Autodesk Fusion 360 part; units mm, degrees
(part 4 of 4)
equation "d8976 = ( fb_y0 + fb_d - 2 * fb_t ) + sk_ref"
equation "d8977 = ( -pod_d / 2 + decor_d - dr_back_t ) + sk_ref"
equation "d8978 = ( op_z0 ) * ( 1 )"
equation "d8979 = ( fb_z0 + fb_h ) - ( op_z0 )"
equation "d8981 = sk_ref"
equation "d8982 = sk_ref"
equation "d8983 = ( ( ( ( fg_rc + dr_fo ) - ( fg_vis_zb * fg_rnz ) ) / fg_rnx ) ) + sk_ref"
equation "d8984 = ( ( -( -( ( dr_fc - dr_fo - dr_fny * ( -pod_d / 2 + dr_fo ) ) / dr_fnx ) ) ) ) + sk_ref"
equation "d8985 = ( ( -( ( -( ( dr_fc - dr_fo - dr_fny * ( -pod_d / 2 + dr_fo ) ) / dr_fnx ) + 0 mm + fr_w ) ) ) ) + sk_ref"
equation "d8986 = ( ( ( ( fg_rc + dr_fo + fr_w ) - ( ( ( fg_vis_zb + 0 mm + fr_w ) ) * fg_rnz ) ) / fg_rnx ) ) + sk_ref"
equation "d8987 = ( ( ( fg_rnx * fg_vis_zb ) / fg_rnx ) ) + sk_ref"
equation "d8988 = ( ( -( -( ( fg_vis_zb + 0 mm + fr_w ) ) ) ) ) + sk_ref"
equation "d8989 = ( ( -pod_d / 2 + dr_fo ) ) * ( 1 )"
equation "d8990 = ( ( -pod_d / 2 + dr_fo + fr_w ) ) - ( ( -pod_d / 2 + dr_fo ) )"
equation "d8992 = fr_t_sk"
equation "d8993 = sk_ref"
equation "d8994 = sk_ref"
equation "d8995 = ( ( -( -( ( dr_fc - dr_fo - dr_fny * ( -pod_d / 2 + dr_fo ) ) / dr_fnx ) ) ) ) + sk_ref"
equation "d8996 = ( ( -( ( -( ( dr_fc - dr_fo - dr_fny * ( -pod_d / 2 + dr_fo ) ) / dr_fnx ) + 0 mm + fr_w ) ) ) ) + sk_ref"
equation "d8997 = ( ( -( -fg_vis_zb ) ) ) + sk_ref"
equation "d8998 = ( ( -( -( ( dr_cc - dr_fo - dr_cny * ( -pod_d / 2 + dr_fo ) ) / dr_cnz ) ) ) ) + sk_ref"
equation "d8999 = ( ( -( ( -( ( dr_cc - dr_fo - dr_cny * ( -pod_d / 2 + dr_fo ) ) / dr_cnz ) + 0 mm + fr_w ) ) ) ) + sk_ref"
equation "d9000 = ( ( -( -( ( fg_vis_zb + 0 mm + fr_w ) ) ) ) ) + sk_ref"
equation "d9001 = ( ( -pod_d / 2 + dr_fo ) ) * ( 1 )"
equation "d9002 = ( ( -pod_d / 2 + dr_fo + fr_w ) ) - ( ( -pod_d / 2 + dr_fo ) )"
equation "d9004 = fr_t_sk"
equation "d9005 = sk_ref"
equation "d9006 = sk_ref"
equation "d9007 = ( ( -( -( ( dr_fc - dr_fo - dr_fny * ( -pod_d / 2 + dr_fo ) ) / dr_fnx ) ) ) ) + sk_ref"
equation "d9008 = ( ( -( -( ( -pod_w / 2 + fix_xtr + ( ( -pod_d / 2 + dr_fo + fr_w ) - -pod_d / 2 ) * ( dt_xr - fix_xtr ) / ( pod_d / 2 - ch_yb ) ) ) ) ) ) + sk_ref"
equation "d9009 = ( ( -( -( ( ( -pod_w / 2 + fix_xtr + ( ( -pod_d / 2 + dr_fo + fr_w ) - -pod_d / 2 ) * ( dt_xr - fix_xtr ) / ( pod_d / 2 - ch_yb ) ) + 0 mm + fr_w ) ) ) ) ) + sk_ref"
equation "d9010 = ( ( -( ( -( ( dr_fc - dr_fo - dr_fny * ( -pod_d / 2 + dr_fo ) ) / dr_fnx ) + 0 mm + fr_w ) ) ) ) + sk_ref"
equation "d9011 = ( ( -( -( ( dr_cc - dr_fo - dr_cny * ( -pod_d / 2 + dr_fo ) ) / dr_cnz ) ) ) ) + sk_ref"
equation "d9012 = ( ( -( ( -( ( dr_cc - dr_fo - dr_cny * ( -pod_d / 2 + dr_fo ) ) / dr_cnz ) + 0 mm + fr_w ) ) ) ) + sk_ref"
equation "d9013 = ( ( -pod_d / 2 + dr_fo ) ) * ( 1 )"
equation "d9014 = ( ( -pod_d / 2 + dr_fo + fr_w ) ) - ( ( -pod_d / 2 + dr_fo ) )"
equation "d9016 = fr_t_sk"
equation "d9017 = sk_ref"
equation "d9018 = sk_ref"
equation "d9019 = ( ( -( -( ( -pod_w / 2 + fix_xtr + ( ( -pod_d / 2 + dr_fo + fr_w ) - -pod_d / 2 ) * ( dt_xr - fix_xtr ) / ( pod_d / 2 - ch_yb ) ) ) ) ) ) + sk_ref"
equation "d9020 = ( ( ( ( ( ( -pod_w / 2 + fix_xtr + ( ( -pod_d / 2 + dr_fo + fr_w ) - -pod_d / 2 ) * ( dt_xr - fix_xtr ) / ( pod_d / 2 - ch_yb ) ) + 0 mm + fr_w ) ) * fg_dnz ) / fg_dnz ) ) + sk_ref"
equation "d9021 = ( ( -( -( ( dr_cc - dr_fo - dr_cny * ( -pod_d / 2 + dr_fo ) ) / dr_cnz ) ) ) ) + sk_ref"
equation "d9022 = ( ( ( ( fg_dc + dr_fo ) - ( fg_dnx * ( ( -pod_w / 2 + fix_xtr + ( ( -pod_d / 2 + dr_fo + fr_w ) - -pod_d / 2 ) * ( dt_xr - fix_xtr ) / ( pod_d / 2 - ch_yb ) ) ) ) ) / fg_dnz ) ) + sk_ref"
equation "d9023 = ( ( ( ( fg_dc + dr_fo + fr_w ) - ( fg_dnx * ( ( ( -pod_w / 2 + fix_xtr + ( ( -pod_d / 2 + dr_fo + fr_w ) - -pod_d / 2 ) * ( dt_xr - fix_xtr ) / ( pod_d / 2 - ch_yb ) ) + 0 mm + fr_w ) ) ) ) / fg_dnz ) ) + sk_ref"
equation "d9024 = ( ( -( ( -( ( dr_cc - dr_fo - dr_cny * ( -pod_d / 2 + dr_fo ) ) / dr_cnz ) + 0 mm + fr_w ) ) ) ) + sk_ref"
equation "d9025 = ( ( -pod_d / 2 + dr_fo ) ) * ( 1 )"
equation "d9026 = ( ( -pod_d / 2 + dr_fo + fr_w ) ) - ( ( -pod_d / 2 + dr_fo ) )"
equation "d9028 = fr_t_sk"
equation "d9029 = sk_ref"
equation "d9030 = sk_ref"
equation "d9031 = ( ( ( ( ( -pod_w / 2 + fix_xtr + ( ( -pod_d / 2 + dr_fo + fr_w ) - -pod_d / 2 ) * ( dt_xr - fix_xtr ) / ( pod_d / 2 - ch_yb ) ) ) * fg_dnz ) / fg_dnz ) ) + sk_ref"
equation "d9032 = ( ( ( ( ( fg_dc + dr_fo ) ) * fg_rnz - ( ( ( fg_rc + dr_fo ) ) * fg_dnz ) ) / ( fg_dnx * fg_rnz - ( fg_rnx * fg_dnz ) ) ) ) + sk_ref"
equation "d9033 = ( ( ( ( ( fg_dc + dr_fo + fr_w ) ) * fg_rnz - ( ( ( fg_rc + dr_fo + fr_w ) ) * fg_dnz ) ) / ( fg_dnx * fg_rnz - ( fg_rnx * fg_dnz ) ) ) ) + sk_ref"
equation "d9034 = ( ( ( ( ( ( -pod_w / 2 + fix_xtr + ( ( -pod_d / 2 + dr_fo + fr_w ) - -pod_d / 2 ) * ( dt_xr - fix_xtr ) / ( pod_d / 2 - ch_yb ) ) + 0 mm + fr_w ) ) * fg_dnz ) / fg_dnz ) ) + sk_ref"
equation "d9035 = ( ( ( ( fg_dc + dr_fo ) - ( fg_dnx * ( ( -pod_w / 2 + fix_xtr + ( ( -pod_d / 2 + dr_fo + fr_w ) - -pod_d / 2 ) * ( dt_xr - fix_xtr ) / ( pod_d / 2 - ch_yb ) ) ) ) ) / fg_dnz ) ) + sk_ref"
equation "d9036 = ( ( ( fg_dnx * ( ( fg_rc + dr_fo ) ) - ( fg_rnx * ( ( fg_dc + dr_fo ) ) ) ) / ( fg_dnx * fg_rnz - ( fg_rnx * fg_dnz ) ) ) ) + sk_ref"
equation "d9037 = ( ( ( fg_dnx * ( ( fg_rc + dr_fo + fr_w ) ) - ( fg_rnx * ( ( fg_dc + dr_fo + fr_w ) ) ) ) / ( fg_dnx * fg_rnz - ( fg_rnx * fg_dnz ) ) ) ) + sk_ref"
equation "d9038 = ( ( ( ( fg_dc + dr_fo + fr_w ) - ( fg_dnx * ( ( ( -pod_w / 2 + fix_xtr + ( ( -pod_d / 2 + dr_fo + fr_w ) - -pod_d / 2 ) * ( dt_xr - fix_xtr ) / ( pod_d / 2 - ch_yb ) ) + 0 mm + fr_w ) ) ) ) / fg_dnz ) ) + sk_ref"
equation "d9039 = ( ( -pod_d / 2 + dr_fo ) ) * ( 1 )"
equation "d9040 = ( ( -pod_d / 2 + dr_fo + fr_w ) ) - ( ( -pod_d / 2 + dr_fo ) )"
equation "d9042 = fr_t_sk"
equation "d9043 = sk_ref"
equation "d9044 = sk_ref"
equation "d9045 = ( ( ( ( ( fg_dc + dr_fo ) ) * fg_rnz - ( ( ( fg_rc + dr_fo ) ) * fg_dnz ) ) / ( fg_dnx * fg_rnz - ( fg_rnx * fg_dnz ) ) ) ) + sk_ref"
equation "d9046 = ( ( ( ( fg_rc + dr_fo ) - ( fg_vis_zb * fg_rnz ) ) / fg_rnx ) ) + sk_ref"
equation "d9047 = ( ( ( ( fg_rc + dr_fo + fr_w ) - ( ( ( fg_vis_zb + 0 mm + fr_w ) ) * fg_rnz ) ) / fg_rnx ) ) + sk_ref"
equation "d9048 = ( ( ( ( ( fg_dc + dr_fo + fr_w ) ) * fg_rnz - ( ( ( fg_rc + dr_fo + fr_w ) ) * fg_dnz ) ) / ( fg_dnx * fg_rnz - ( fg_rnx * fg_dnz ) ) ) ) + sk_ref"
equation "d9049 = ( ( ( fg_dnx * ( ( fg_rc + dr_fo ) ) - ( fg_rnx * ( ( fg_dc + dr_fo ) ) ) ) / ( fg_dnx * fg_rnz - ( fg_rnx * fg_dnz ) ) ) ) + sk_ref"
equation "d9050 = ( ( ( fg_rnx * fg_vis_zb ) / fg_rnx ) ) + sk_ref"
equation "d9051 = ( ( ( fg_rnx * ( ( fg_vis_zb + 0 mm + fr_w ) ) ) / fg_rnx ) ) + sk_ref"
equation "d9052 = ( ( ( fg_dnx * ( ( fg_rc + dr_fo + fr_w ) ) - ( fg_rnx * ( ( fg_dc + dr_fo + fr_w ) ) ) ) / ( fg_dnx * fg_rnz - ( fg_rnx * fg_dnz ) ) ) ) + sk_ref"
equation "d9053 = ( ( -pod_d / 2 + dr_fo ) ) * ( 1 )"
equation "d9054 = ( ( -pod_d / 2 + dr_fo + fr_w ) ) - ( ( -pod_d / 2 + dr_fo ) )"
equation "d9056 = fr_t_sk"
equation "d9057 = sk_ref"
equation "d9058 = sk_ref"
equation "d9059 = ( ( ( ( fg_rc + dr_fo ) - ( fg_vis_zb * fg_rnz ) ) / fg_rnx ) ) + sk_ref"
equation "d9060 = ( ( -( ( -pod_w / 2 + dr_fo ) ) ) ) + sk_ref"
equation "d9061 = ( ( -( ( -pod_w / 2 + dr_fo + fr_wb ) ) ) ) + sk_ref"
equation "d9062 = ( ( ( ( fg_rc + dr_fo + fr_w ) - ( ( ( fg_vis_zb + 0 mm + fr_wbot ) ) * fg_rnz ) ) / fg_rnx ) ) + sk_ref"
equation "d9063 = ( ( ( fg_rnx * fg_vis_zb ) / fg_rnx ) ) + sk_ref"
equation "d9064 = ( ( -( -( ( fg_vis_zb + 0 mm + fr_wbot ) ) ) ) ) + sk_ref"
equation "d9065 = ( ( -pod_d / 2 + decor_d - dr_back_t - fr_w ) ) * ( 1 )"
equation "d9066 = ( ( -pod_d / 2 + decor_d - dr_back_t ) ) - ( ( -pod_d / 2 + decor_d - dr_back_t - fr_w ) )"
equation "d9068 = fr_t_pnl"
equation "d9069 = sk_ref"
equation "d9070 = sk_ref"
equation "d9071 = ( ( -( ( -pod_w / 2 + dr_fo ) ) ) ) + sk_ref"
equation "d9072 = ( ( -( ( -pod_w / 2 + dr_fo + fr_wb ) ) ) ) + sk_ref"
equation "d9073 = ( ( -( -fg_vis_zb ) ) ) + sk_ref"
equation "d9074 = ( ( -( ( -pod_h + dr_fo ) ) ) ) + sk_ref"
equation "d9075 = ( ( -( ( -pod_h + dr_fo + fr_w ) ) ) ) + sk_ref"
equation "d9076 = ( ( -( -( ( fg_vis_zb + 0 mm + fr_wbot ) ) ) ) ) + sk_ref"
equation "d9077 = ( ( -pod_d / 2 + decor_d - dr_back_t - fr_w ) ) * ( 1 )"
equation "d9078 = ( ( -pod_d / 2 + decor_d - dr_back_t ) ) - ( ( -pod_d / 2 + decor_d - dr_back_t - fr_w ) )"
equation "d9080 = fr_t_pnl"
equation "d9081 = sk_ref"
equation "d9082 = sk_ref"
equation "d9083 = ( ( -( ( -pod_w / 2 + dr_fo ) ) ) ) + sk_ref"
equation "d9084 = ( ( -( -( ( -pod_w / 2 + dt_xr ) ) ) ) ) + sk_ref"
equation "d9085 = ( ( -( -( ( ( -pod_w / 2 + dt_xr ) + 0 mm + fr_w ) ) ) ) ) + sk_ref"
equation "d9086 = ( ( -( ( -pod_w / 2 + dr_fo + fr_wb ) ) ) ) + sk_ref"
equation "d9087 = ( ( -( ( -pod_h + dr_fo ) ) ) ) + sk_ref"
equation "d9088 = ( ( -( ( -pod_h + dr_fo + fr_w ) ) ) ) + sk_ref"
equation "d9089 = ( ( -pod_d / 2 + decor_d - dr_back_t - fr_w ) ) * ( 1 )"
equation "d9090 = ( ( -pod_d / 2 + decor_d - dr_back_t ) ) - ( ( -pod_d / 2 + decor_d - dr_back_t - fr_w ) )"
equation "d9092 = fr_t_sk"
equation "d9093 = sk_ref"
equation "d9094 = sk_ref"
equation "d9095 = ( ( -( -( ( -pod_w / 2 + dt_xr ) ) ) ) ) + sk_ref"
equation "d9096 = ( ( -( -( ( ( -pod_w / 2 + dt_xr ) + 0 mm + fr_w ) ) ) ) ) + sk_ref"
equation "d9097 = ( ( -( ( -pod_h + dr_fo ) ) ) ) + sk_ref"
equation "d9098 = ( ( -( -dt_zb ) ) ) + sk_ref"
equation "d9099 = ( ( -( ( -dt_zb + 0 mm + fr_w ) ) ) ) + sk_ref"
equation "d9100 = ( ( -( ( -pod_h + dr_fo + fr_w ) ) ) ) + sk_ref"
equation "d9101 = ( ( -pod_d / 2 + decor_d - dr_back_t - fr_w ) ) * ( 1 )"
equation "d9102 = ( ( -pod_d / 2 + decor_d - dr_back_t ) ) - ( ( -pod_d / 2 + decor_d - dr_back_t - fr_w ) )"
equation "d9104 = fr_t_sk"
equation "d9105 = sk_ref"
equation "d9106 = sk_ref"
equation "d9107 = ( ( -( -( ( -pod_w / 2 + dt_xr ) ) ) ) ) + sk_ref"
equation "d9108 = ( ( ( ( -dt_zb ) * fg_dnz - ( -( ( fg_dc + dr_fo ) ) ) ) / ( -( -fg_dnx ) ) ) ) + sk_ref"
equation "d9109 = ( ( ( ( ( -dt_zb + 0 mm + fr_w ) ) * fg_dnz - ( -( ( fg_dc + dr_fo + fr_w ) ) ) ) / ( -( -fg_dnx ) ) ) ) + sk_ref"
equation "d9110 = ( ( -( -( ( ( -pod_w / 2 + dt_xr ) + 0 mm + fr_w ) ) ) ) ) + sk_ref"
equation "d9111 = ( ( -( -dt_zb ) ) ) + sk_ref"
equation "d9112 = ( ( ( -( fg_dnx * ( ( -dt_zb + 0 mm + fr_w ) ) ) ) / ( -( -fg_dnx ) ) ) ) + sk_ref"
equation "d9113 = ( ( -pod_d / 2 + decor_d - dr_back_t - fr_w ) ) * ( 1 )"
equation "d9114 = ( ( -pod_d / 2 + decor_d - dr_back_t ) ) - ( ( -pod_d / 2 + decor_d - dr_back_t - fr_w ) )"
equation "d9116 = fr_t_pnl"
equation "d9117 = sk_ref"
equation "d9118 = sk_ref"
equation "d9119 = ( ( ( ( -dt_zb ) * fg_dnz - ( -( ( fg_dc + dr_fo ) ) ) ) / ( -( -fg_dnx ) ) ) ) + sk_ref"
equation "d9120 = ( ( ( ( ( fg_dc + dr_fo ) ) * fg_rnz - ( ( ( fg_rc + dr_fo ) ) * fg_dnz ) ) / ( fg_dnx * fg_rnz - ( fg_rnx * fg_dnz ) ) ) ) + sk_ref"
equation "d9121 = ( ( ( ( ( fg_dc + dr_fo + fr_w ) ) * fg_rnz - ( ( ( fg_rc + dr_fo + fr_w ) ) * fg_dnz ) ) / ( fg_dnx * fg_rnz - ( fg_rnx * fg_dnz ) ) ) ) + sk_ref"
equation "d9122 = ( ( ( ( ( -dt_zb + 0 mm + fr_w ) ) * fg_dnz - ( -( ( fg_dc + dr_fo + fr_w ) ) ) ) / ( -( -fg_dnx ) ) ) ) + sk_ref"
equation "d9123 = ( ( ( -( fg_dnx * ( -dt_zb ) ) ) / ( -( -fg_dnx ) ) ) ) + sk_ref"
equation "d9124 = ( ( ( fg_dnx * ( ( fg_rc + dr_fo ) ) - ( fg_rnx * ( ( fg_dc + dr_fo ) ) ) ) / ( fg_dnx * fg_rnz - ( fg_rnx * fg_dnz ) ) ) ) + sk_ref"
equation "d9125 = ( ( ( fg_dnx * ( ( fg_rc + dr_fo + fr_w ) ) - ( fg_rnx * ( ( fg_dc + dr_fo + fr_w ) ) ) ) / ( fg_dnx * fg_rnz - ( fg_rnx * fg_dnz ) ) ) ) + sk_ref"
equation "d9126 = ( ( ( -( fg_dnx * ( ( -dt_zb + 0 mm + fr_w ) ) ) ) / ( -( -fg_dnx ) ) ) ) + sk_ref"
equation "d9127 = ( ( -pod_d / 2 + decor_d - dr_back_t - fr_w ) ) * ( 1 )"
equation "d9128 = ( ( -pod_d / 2 + decor_d - dr_back_t ) ) - ( ( -pod_d / 2 + decor_d - dr_back_t - fr_w ) )"
equation "d9130 = fr_t_pnl"
equation "d9131 = sk_ref"
equation "d9132 = sk_ref"
equation "d9133 = ( ( ( ( ( fg_dc + dr_fo ) ) * fg_rnz - ( ( ( fg_rc + dr_fo ) ) * fg_dnz ) ) / ( fg_dnx * fg_rnz - ( fg_rnx * fg_dnz ) ) ) ) + sk_ref"
equation "d9134 = ( ( ( ( fg_rc + dr_fo ) - ( fg_vis_zb * fg_rnz ) ) / fg_rnx ) ) + sk_ref"
equation "d9135 = ( ( ( ( fg_rc + dr_fo + fr_w ) - ( ( ( fg_vis_zb + 0 mm + fr_wbot ) ) * fg_rnz ) ) / fg_rnx ) ) + sk_ref"
equation "d9136 = ( ( ( ( ( fg_dc + dr_fo + fr_w ) ) * fg_rnz - ( ( ( fg_rc + dr_fo + fr_w ) ) * fg_dnz ) ) / ( fg_dnx * fg_rnz - ( fg_rnx * fg_dnz ) ) ) ) + sk_ref"
equation "d9137 = ( ( ( fg_dnx * ( ( fg_rc + dr_fo ) ) - ( fg_rnx * ( ( fg_dc + dr_fo ) ) ) ) / ( fg_dnx * fg_rnz - ( fg_rnx * fg_dnz ) ) ) ) + sk_ref"
equation "d9138 = ( ( ( fg_rnx * fg_vis_zb ) / fg_rnx ) ) + sk_ref"
equation "d9139 = ( ( ( fg_rnx * ( ( fg_vis_zb + 0 mm + fr_wbot ) ) ) / fg_rnx ) ) + sk_ref"
equation "d9140 = ( ( ( fg_dnx * ( ( fg_rc + dr_fo + fr_w ) ) - ( fg_rnx * ( ( fg_dc + dr_fo + fr_w ) ) ) ) / ( fg_dnx * fg_rnz - ( fg_rnx * fg_dnz ) ) ) ) + sk_ref"
equation "d9141 = ( ( -pod_d / 2 + decor_d - dr_back_t - fr_w ) ) * ( 1 )"
equation "d9142 = ( ( -pod_d / 2 + decor_d - dr_back_t ) ) - ( ( -pod_d / 2 + decor_d - dr_back_t - fr_w ) )"
equation "d9144 = fr_t_pnl"
equation "d9145 = sk_ref"
equation "d9146 = sk_ref"
equation "d9147 = ( ( ( ( fg_rc + dr_fo + fr_w ) - ( ( fg_vis_zb + fr_h1 ) * fg_rnz ) ) / fg_rnx ) ) + sk_ref"
equation "d9148 = ( ( ( ( dr_fc - dr_fo - dr_fny * ( -pod_d / 2 + dr_fo ) ) / dr_fnx ) - fr_w ) ) + sk_ref"
equation "d9149 = ( ( ( ( fg_rc + dr_fo + fr_w ) - ( ( fg_vis_zb + fr_h1 + fr_w ) * fg_rnz ) ) / fg_rnx ) ) + sk_ref"
equation "d9150 = ( ( ( fg_rnx * ( fg_vis_zb + fr_h1 ) ) / fg_rnx ) ) + sk_ref"
equation "d9151 = ( fg_vis_zb + fr_h1 + fr_w ) + sk_ref"
equation "d9152 = ( ( -pod_d / 2 + dr_fo ) ) * ( 1 )"
equation "d9153 = ( ( -pod_d / 2 + dr_fo + fr_w ) ) - ( ( -pod_d / 2 + dr_fo ) )"
equation "d9155 = fr_t_sk"
equation "d9156 = sk_ref"
equation "d9157 = sk_ref"
equation "d9158 = ( ( ( ( fg_dc + dr_fo + fr_w ) - ( ( fb_z0 - fr_w ) * fg_dnz ) ) / fg_dnx ) ) + sk_ref"
equation "d9159 = ( ( ( ( dr_fc - dr_fo - dr_fny * ( -pod_d / 2 + dr_fo ) ) / dr_fnx ) - fr_w ) ) + sk_ref"
equation "d9160 = ( ( ( ( fg_dc + dr_fo + fr_w ) - ( ( fb_z0 - fr_w + fr_w ) * fg_dnz ) ) / fg_dnx ) ) + sk_ref"
equation "d9161 = ( ( ( fg_dnx * ( fb_z0 - fr_w ) ) / fg_dnx ) ) + sk_ref"
equation "d9162 = ( fb_z0 - fr_w + fr_w ) + sk_ref"
equation "d9163 = ( ( -pod_d / 2 + dr_fo ) ) * ( 1 )"
equation "d9164 = ( ( -pod_d / 2 + dr_fo + fr_w ) ) - ( ( -pod_d / 2 + dr_fo ) )"
equation "d9166 = fr_t"
equation "d9167 = sk_ref"
equation "d9168 = sk_ref"
equation "d9169 = ( ( ( ( fg_dc + dr_fo + fr_w ) - ( ( ( ( fb_z0 + ( ( dr_cc - dr_fo - dr_cny * ( -pod_d / 2 + dr_fo ) ) / dr_cnz ) - fr_w ) / 2 - fr_w / 2 ) ) * fg_dnz ) ) / fg_dnx ) ) + sk_ref"
equation "d9170 = ( ( ( ( dr_fc - dr_fo - dr_fny * ( -pod_d / 2 + dr_fo ) ) / dr_fnx ) - fr_w ) ) + sk_ref"
equation "d9171 = ( ( ( ( fg_dc + dr_fo + fr_w ) - ( ( ( ( fb_z0 + ( ( dr_cc - dr_fo - dr_cny * ( -pod_d / 2 + dr_fo ) ) / dr_cnz ) - fr_w ) / 2 - fr_w / 2 ) + fr_w ) * fg_dnz ) ) / fg_dnx ) ) + sk_ref"
equation "d9172 = ( ( ( fg_dnx * ( ( ( fb_z0 + ( ( dr_cc - dr_fo - dr_cny * ( -pod_d / 2 + dr_fo ) ) / dr_cnz ) - fr_w ) / 2 - fr_w / 2 ) ) ) / fg_dnx ) ) + sk_ref"
equation "d9173 = ( ( ( fb_z0 + ( ( dr_cc - dr_fo - dr_cny * ( -pod_d / 2 + dr_fo ) ) / dr_cnz ) - fr_w ) / 2 - fr_w / 2 ) + fr_w ) + sk_ref"
equation "d9174 = ( ( -pod_d / 2 + dr_fo ) ) * ( 1 )"
equation "d9175 = ( ( -pod_d / 2 + dr_fo + fr_w ) ) - ( ( -pod_d / 2 + dr_fo ) )"
equation "d9177 = fr_t_sk"
equation "d9178 = sk_ref"
equation "d9179 = sk_ref"
equation "d9180 = ( ( pod_w / 2 - dr_fo - fr_wb ) ) + sk_ref"
equation "d9181 = ( ( -pod_w / 2 + dt_xr + fr_w ) ) + sk_ref"
equation "d9182 = ( fg_vis_zt ) + sk_ref"
equation "d9183 = ( fg_vis_zt + fr_wband ) + sk_ref"
equation "d9184 = ( ( -pod_d / 2 + decor_d - dr_back_t - fr_w ) ) * ( 1 )"
equation "d9185 = ( ( -pod_d / 2 + decor_d - dr_back_t ) ) - ( ( -pod_d / 2 + decor_d - dr_back_t - fr_w ) )"
equation "d9187 = fr_t_pnl"
equation "d9188 = sk_ref"
equation "d9189 = sk_ref"
equation "d9190 = ( ( ( -( ( ( pod_w / 2 - dr_fo ) ) * ( -dr_fny ) ) ) / ( -( -dr_fny ) ) ) ) + sk_ref"
equation "d9191 = ( ( ( ( -dr_fc + dr_fo + fr_w ) - ( ( ( -pod_d / 2 + decor_d - dr_back_t - fr_w ) ) * ( -dr_fny ) ) ) / ( -dr_fnx ) ) ) + sk_ref"
equation "d9192 = ( ( ( -( ( ( ( dr_fc - dr_fo - dr_fny * ( -pod_d / 2 + dr_fo ) ) / dr_fnx ) ) * ( -dr_fny ) ) ) / ( -( -dr_fny ) ) ) ) + sk_ref"
equation "d9193 = ( ( ( ( -dr_fnx ) * ( ( ( dr_fc - dr_fo - dr_fny * ( -pod_d / 2 + dr_fo ) ) / dr_fnx ) ) - ( ( -dr_fc + dr_fo ) ) ) / ( -( -dr_fny ) ) ) ) + sk_ref"
equation "d9194 = ( ( ( ( -dr_fnx ) * ( ( pod_w / 2 - dr_fo ) ) - ( ( -dr_fc + dr_fo ) ) ) / ( -( -dr_fny ) ) ) ) + sk_ref"
equation "d9195 = ( ( -pod_d / 2 + decor_d - dr_back_t - fr_w ) ) + sk_ref"
equation "d9196 = ( ( ( ( -dr_fnx ) * ( ( ( dr_fc - dr_fo - dr_fny * ( -pod_d / 2 + dr_fo ) ) / dr_fnx ) ) - ( ( -dr_fc + dr_fo + fr_w ) ) ) / ( -( -dr_fny ) ) ) ) + sk_ref"
equation "d9197 = ( fg_vis_zb ) * ( 1 )"
equation "d9198 = ( fg_vis_zb + fr_w ) - ( fg_vis_zb )"
equation "d9200 = fr_t_sk"
equation "d9201 = sk_ref"
equation "d9202 = sk_ref"
equation "d9203 = ( ( ( -( ( ( pod_w / 2 - dr_fo ) ) * ( -dr_fny ) ) ) / ( -( -dr_fny ) ) ) ) + sk_ref"
equation "d9204 = ( ( ( ( -dr_fc + dr_fo + fr_w ) - ( ( ( -pod_d / 2 + decor_d - dr_back_t - fr_w ) ) * ( -dr_fny ) ) ) / ( -dr_fnx ) ) ) + sk_ref"
equation "d9205 = ( ( ( -( ( ( ( dr_fc - dr_fo - dr_fny * ( -pod_d / 2 + dr_fo ) ) / dr_fnx ) ) * ( -dr_fny ) ) ) / ( -( -dr_fny ) ) ) ) + sk_ref"
equation "d9206 = ( ( ( ( -dr_fnx ) * ( ( ( dr_fc - dr_fo - dr_fny * ( -pod_d / 2 + dr_fo ) ) / dr_fnx ) ) - ( ( -dr_fc + dr_fo ) ) ) / ( -( -dr_fny ) ) ) ) + sk_ref"
equation "d9207 = ( ( ( ( -dr_fnx ) * ( ( pod_w / 2 - dr_fo ) ) - ( ( -dr_fc + dr_fo ) ) ) / ( -( -dr_fny ) ) ) ) + sk_ref"
equation "d9208 = ( ( -pod_d / 2 + decor_d - dr_back_t - fr_w ) ) + sk_ref"
equation "d9209 = ( ( ( ( -dr_fnx ) * ( ( ( dr_fc - dr_fo - dr_fny * ( -pod_d / 2 + dr_fo ) ) / dr_fnx ) ) - ( ( -dr_fc + dr_fo + fr_w ) ) ) / ( -( -dr_fny ) ) ) ) + sk_ref"
equation "d9210 = ( fb_z0 - fr_w ) * ( 1 )"
equation "d9211 = ( fb_z0 - fr_w + fr_w ) - ( fb_z0 - fr_w )"
equation "d9213 = fr_t"
equation "d9214 = ( fb_z0 + fb_h - fr_w ) - ( fg_vis_zb )"
equation "d9220 = ( ( ( dr_cc - dr_fo - dr_cny * ( -pod_d / 2 + dr_fo ) ) / dr_cnz ) - fr_w ) - ( fg_vis_zb )"
equation "d9226 = sk_ref"
equation "d9227 = sk_ref"
equation "d9228 = ( ( ( ( -dr_cny ) * ( ( pod_h - dr_fo ) ) ) / ( -dr_cny ) ) ) + sk_ref"
equation "d9229 = ( ( ( ( -dr_cny ) * ( ( -pod_d / 2 + decor_d - dr_back_t - fr_w ) ) - ( ( -dr_cc + dr_fo + fr_w ) ) ) / ( -( -dr_cnz ) ) ) ) + sk_ref"
equation "d9230 = ( ( ( ( -dr_cny ) * ( ( ( dr_cc - dr_fo - dr_cny * ( -pod_d / 2 + dr_fo ) ) / dr_cnz ) ) ) / ( -dr_cny ) ) ) + sk_ref"
equation "d9231 = ( ( -pod_d / 2 + dr_fo ) ) + sk_ref"
equation "d9232 = ( ( ( ( -dr_cc + dr_fo ) - ( ( ( pod_h - dr_fo ) ) * ( -dr_cnz ) ) ) / ( -dr_cny ) ) ) + sk_ref"
equation "d9233 = ( ( -pod_d / 2 + decor_d - dr_back_t - fr_w ) ) + sk_ref"
equation "d9234 = ( ( ( ( -dr_cc + dr_fo + fr_w ) - ( ( ( ( dr_cc - dr_fo - dr_cny * ( -pod_d / 2 + dr_fo ) ) / dr_cnz ) ) * ( -dr_cnz ) ) ) / ( -dr_cny ) ) ) + sk_ref"
equation "d9235 = ( ( -pod_w / 2 + dt_xr + fr_w ) ) * ( 1 )"
equation "d9236 = ( ( -pod_w / 2 + dt_xr + fr_w ) + fr_w ) - ( ( -pod_w / 2 + dt_xr + fr_w ) )"
equation "d9238 = fr_t_sk"
equation "d9239 = ( ( ( ( dr_fc - dr_fo - dr_fny * ( -pod_d / 2 + dr_fo ) ) / dr_fnx ) - 2 * fr_w ) ) - ( ( -pod_w / 2 + dt_xr + fr_w ) )"
equation "d9245 = sk_ref"
equation "d9246 = sk_ref"
equation "d9247 = ( ( ( dr_jc - ( ( ( -pod_d / 2 + dr_fo + fr_w ) ) * dr_jny ) ) / dr_jnx ) ) + sk_ref"
equation "d9248 = ( ( ( dr_jc - ( ( ( -pod_d / 2 + decor_d - dr_back_t - fr_w ) ) * dr_jny ) ) / dr_jnx ) ) + sk_ref"
equation "d9249 = ( ( ( ( dr_jc + fr_w ) - ( ( ( -pod_d / 2 + decor_d - dr_back_t - fr_w ) ) * dr_jny ) ) / dr_jnx ) ) + sk_ref"
equation "d9250 = ( ( ( ( dr_jc + fr_w ) - ( ( ( -pod_d / 2 + dr_fo + fr_w ) ) * dr_jny ) ) / dr_jnx ) ) + sk_ref"
equation "d9251 = ( ( ( dr_jnx * ( ( -pod_d / 2 + decor_d - dr_back_t - fr_w ) ) ) / dr_jnx ) ) + sk_ref"
equation "d9252 = ( ( ( dr_jnx * ( ( -pod_d / 2 + dr_fo + fr_w ) ) ) / dr_jnx ) ) + sk_ref"
equation "d9253 = ( fg_vis_zt ) * ( 1 )"
equation "d9254 = ( fg_vis_zt + fr_w ) - ( fg_vis_zt )"
equation "d9256 = fr_t_sk"
equation "d9257 = sk_ref"
equation "d9258 = sk_ref"
equation "d9259 = ( jf_x ) + sk_ref"
equation "d9260 = ( jf_z1 ) + sk_ref"
equation "d9261 = fr_hole_jf"
equation "d9262 = ( jf_x ) + sk_ref"
equation "d9263 = ( jf_z2 ) + sk_ref"
equation "d9264 = fr_hole_jf"
equation "d9265 = ( jf_x ) + sk_ref"
equation "d9266 = ( jf_z3 ) + sk_ref"
equation "d9267 = fr_hole_jf"
equation "d9268 = ( jf_x ) + sk_ref"
equation "d9269 = ( jf_z4 ) + sk_ref"
equation "d9270 = fr_hole_jf"
equation "d9271 = ( jf_x ) + sk_ref"
equation "d9272 = ( jf_z5 ) + sk_ref"
equation "d9273 = fr_hole_jf"
equation "d9274 = ( jf_x ) + sk_ref"
equation "d9275 = ( jf_z6 ) + sk_ref"
equation "d9276 = fr_hole_jf"
equation "d9277 = ( -pod_d / 2 + decor_d - dr_back_t - fr_t_pnl - 1 mm ) * ( 1 )"
equation "d9278 = ( -pod_d / 2 + decor_d - dr_back_t + 0.5 mm ) - ( -pod_d / 2 + decor_d - dr_back_t - fr_t_pnl - 1 mm )"
equation "d9280 = sk_ref"
equation "d9281 = sk_ref"
equation "d9282 = ( dr_pl0x + ( dr_pl1x - dr_pl0x ) * ( ( dr_sc_clear + 0 * ( dr_pe0 - dr_sc_clear - dr_sc_clear ) / 1 ) / dr_pe0 ) ) + sk_ref"
equation "d9283 = ( dr_pl0z + ( dr_pl1z - dr_pl0z ) * ( ( dr_sc_clear + 0 * ( dr_pe0 - dr_sc_clear - dr_sc_clear ) / 1 ) / dr_pe0 ) ) + sk_ref"
equation "d9284 = fr_hole_rn"
equation "d9285 = ( dr_pl0x + ( dr_pl1x - dr_pl0x ) * ( ( dr_sc_clear + 1 * ( dr_pe0 - dr_sc_clear - dr_sc_clear ) / 1 ) / dr_pe0 ) ) + sk_ref"
equation "d9286 = ( dr_pl0z + ( dr_pl1z - dr_pl0z ) * ( ( dr_sc_clear + 1 * ( dr_pe0 - dr_sc_clear - dr_sc_clear ) / 1 ) / dr_pe0 ) ) + sk_ref"
equation "d9287 = fr_hole_rn"
equation "d9288 = ( -pod_d / 2 + decor_d - dr_back_t - fr_t_pnl - 1 mm ) * ( 1 )"
equation "d9289 = ( -pod_d / 2 + decor_d - dr_back_t + 0.5 mm ) - ( -pod_d / 2 + decor_d - dr_back_t - fr_t_pnl - 1 mm )"
equation "d9291 = sk_ref"
equation "d9292 = sk_ref"
equation "d9293 = ( dr_pl1x + ( dr_pl2x - dr_pl1x ) * ( ( dr_sc_clear + 0 * ( dr_pe1 - dr_sc_clear - dr_sc_clear ) / 5 ) / dr_pe1 ) ) + sk_ref"
equation "d9294 = ( dr_pl1z + ( dr_pl2z - dr_pl1z ) * ( ( dr_sc_clear + 0 * ( dr_pe1 - dr_sc_clear - dr_sc_clear ) / 5 ) / dr_pe1 ) ) + sk_ref"
equation "d9295 = fr_hole_rn"
equation "d9296 = ( dr_pl1x + ( dr_pl2x - dr_pl1x ) * ( ( dr_sc_clear + 1 * ( dr_pe1 - dr_sc_clear - dr_sc_clear ) / 5 ) / dr_pe1 ) ) + sk_ref"
equation "d9297 = ( dr_pl1z + ( dr_pl2z - dr_pl1z ) * ( ( dr_sc_clear + 1 * ( dr_pe1 - dr_sc_clear - dr_sc_clear ) / 5 ) / dr_pe1 ) ) + sk_ref"
equation "d9298 = fr_hole_rn"
equation "d9299 = ( dr_pl1x + ( dr_pl2x - dr_pl1x ) * ( ( dr_sc_clear + 2 * ( dr_pe1 - dr_sc_clear - dr_sc_clear ) / 5 ) / dr_pe1 ) ) + sk_ref"
equation "d9300 = ( dr_pl1z + ( dr_pl2z - dr_pl1z ) * ( ( dr_sc_clear + 2 * ( dr_pe1 - dr_sc_clear - dr_sc_clear ) / 5 ) / dr_pe1 ) ) + sk_ref"
equation "d9301 = fr_hole_rn"
equation "d9302 = ( dr_pl1x + ( dr_pl2x - dr_pl1x ) * ( ( dr_sc_clear + 3 * ( dr_pe1 - dr_sc_clear - dr_sc_clear ) / 5 ) / dr_pe1 ) ) + sk_ref"
equation "d9303 = ( dr_pl1z + ( dr_pl2z - dr_pl1z ) * ( ( dr_sc_clear + 3 * ( dr_pe1 - dr_sc_clear - dr_sc_clear ) / 5 ) / dr_pe1 ) ) + sk_ref"
equation "d9304 = fr_hole_rn"
equation "d9305 = ( dr_pl1x + ( dr_pl2x - dr_pl1x ) * ( ( dr_sc_clear + 4 * ( dr_pe1 - dr_sc_clear - dr_sc_clear ) / 5 ) / dr_pe1 ) ) + sk_ref"
equation "d9306 = ( dr_pl1z + ( dr_pl2z - dr_pl1z ) * ( ( dr_sc_clear + 4 * ( dr_pe1 - dr_sc_clear - dr_sc_clear ) / 5 ) / dr_pe1 ) ) + sk_ref"
equation "d9307 = fr_hole_rn"
equation "d9308 = ( dr_pl1x + ( dr_pl2x - dr_pl1x ) * ( ( dr_sc_clear + 5 * ( dr_pe1 - dr_sc_clear - dr_sc_clear ) / 5 ) / dr_pe1 ) ) + sk_ref"
equation "d9309 = ( dr_pl1z + ( dr_pl2z - dr_pl1z ) * ( ( dr_sc_clear + 5 * ( dr_pe1 - dr_sc_clear - dr_sc_clear ) / 5 ) / dr_pe1 ) ) + sk_ref"
equation "d9310 = fr_hole_rn"
equation "d9311 = ( -pod_d / 2 + decor_d - dr_back_t - fr_t_pnl - 1 mm ) * ( 1 )"
equation "d9312 = ( -pod_d / 2 + decor_d - dr_back_t + 0.5 mm ) - ( -pod_d / 2 + decor_d - dr_back_t - fr_t_pnl - 1 mm )"
equation "d9314 = sk_ref"
equation "d9315 = sk_ref"
equation "d9316 = ( dr_pl2x + ( dr_pl3x - dr_pl2x ) * ( ( dr_sc_b08 + 0 * ( dr_pe2 - dr_sc_b08 - dr_sc_clear ) / 2 ) / dr_pe2 ) ) + sk_ref"
equation "d9317 = ( dr_pl2z + ( dr_pl3z - dr_pl2z ) * ( ( dr_sc_b08 + 0 * ( dr_pe2 - dr_sc_b08 - dr_sc_clear ) / 2 ) / dr_pe2 ) ) + sk_ref"
equation "d9318 = fr_hole_rn"
equation "d9319 = ( dr_pl2x + ( dr_pl3x - dr_pl2x ) * ( ( dr_sc_b08 + 1 * ( dr_pe2 - dr_sc_b08 - dr_sc_clear ) / 2 ) / dr_pe2 ) ) + sk_ref"
equation "d9320 = ( dr_pl2z + ( dr_pl3z - dr_pl2z ) * ( ( dr_sc_b08 + 1 * ( dr_pe2 - dr_sc_b08 - dr_sc_clear ) / 2 ) / dr_pe2 ) ) + sk_ref"
equation "d9321 = fr_hole_rn"
equation "d9322 = ( dr_pl2x + ( dr_pl3x - dr_pl2x ) * ( ( dr_sc_b08 + 2 * ( dr_pe2 - dr_sc_b08 - dr_sc_clear ) / 2 ) / dr_pe2 ) ) + sk_ref"
equation "d9323 = ( dr_pl2z + ( dr_pl3z - dr_pl2z ) * ( ( dr_sc_b08 + 2 * ( dr_pe2 - dr_sc_b08 - dr_sc_clear ) / 2 ) / dr_pe2 ) ) + sk_ref"
equation "d9324 = fr_hole_rn"
equation "d9325 = ( -pod_d / 2 + decor_d - dr_back_t - fr_t_pnl - 1 mm ) * ( 1 )"
equation "d9326 = ( -pod_d / 2 + decor_d - dr_back_t + 0.5 mm ) - ( -pod_d / 2 + decor_d - dr_back_t - fr_t_pnl - 1 mm )"
equation "d9328 = sk_ref"
equation "d9329 = sk_ref"
equation "d9330 = ( dr_pl4x + ( dr_pl5x - dr_pl4x ) * ( ( dr_sc_clear + 0 * ( dr_pe4 - dr_sc_clear - dr_sc_clear ) / 1 ) / dr_pe4 ) ) + sk_ref"
equation "d9331 = ( dr_pl4z + ( dr_pl5z - dr_pl4z ) * ( ( dr_sc_clear + 0 * ( dr_pe4 - dr_sc_clear - dr_sc_clear ) / 1 ) / dr_pe4 ) ) + sk_ref"
equation "d9332 = fr_hole_rn"
equation "d9333 = ( dr_pl4x + ( dr_pl5x - dr_pl4x ) * ( ( dr_sc_clear + 1 * ( dr_pe4 - dr_sc_clear - dr_sc_clear ) / 1 ) / dr_pe4 ) ) + sk_ref"
equation "d9334 = ( dr_pl4z + ( dr_pl5z - dr_pl4z ) * ( ( dr_sc_clear + 1 * ( dr_pe4 - dr_sc_clear - dr_sc_clear ) / 1 ) / dr_pe4 ) ) + sk_ref"
equation "d9335 = fr_hole_rn"
equation "d9336 = ( -pod_d / 2 + decor_d - dr_back_t - fr_t_pnl - 1 mm ) * ( 1 )"
equation "d9337 = ( -pod_d / 2 + decor_d - dr_back_t + 0.5 mm ) - ( -pod_d / 2 + decor_d - dr_back_t - fr_t_pnl - 1 mm )"
equation "d9339 = sk_ref"
equation "d9340 = sk_ref"
equation "d9341 = ( dr_pl5x + ( dr_pl6x - dr_pl5x ) * ( ( dr_sc_clear + 0 * ( dr_pe5 - dr_sc_clear - dr_sc_clear ) / 2 ) / dr_pe5 ) ) + sk_ref"
equation "d9342 = ( dr_pl5z + ( dr_pl6z - dr_pl5z ) * ( ( dr_sc_clear + 0 * ( dr_pe5 - dr_sc_clear - dr_sc_clear ) / 2 ) / dr_pe5 ) ) + sk_ref"
equation "d9343 = fr_hole_rn"
equation "d9344 = ( dr_pl5x + ( dr_pl6x - dr_pl5x ) * ( ( dr_sc_clear + 1 * ( dr_pe5 - dr_sc_clear - dr_sc_clear ) / 2 ) / dr_pe5 ) ) + sk_ref"
equation "d9345 = ( dr_pl5z + ( dr_pl6z - dr_pl5z ) * ( ( dr_sc_clear + 1 * ( dr_pe5 - dr_sc_clear - dr_sc_clear ) / 2 ) / dr_pe5 ) ) + sk_ref"
equation "d9346 = fr_hole_rn"
equation "d9347 = ( dr_pl5x + ( dr_pl6x - dr_pl5x ) * ( ( dr_sc_clear + 2 * ( dr_pe5 - dr_sc_clear - dr_sc_clear ) / 2 ) / dr_pe5 ) ) + sk_ref"
equation "d9348 = ( dr_pl5z + ( dr_pl6z - dr_pl5z ) * ( ( dr_sc_clear + 2 * ( dr_pe5 - dr_sc_clear - dr_sc_clear ) / 2 ) / dr_pe5 ) ) + sk_ref"
equation "d9349 = fr_hole_rn"
equation "d9350 = ( -pod_d / 2 + decor_d - dr_back_t - fr_t_pnl - 1 mm ) * ( 1 )"
equation "d9351 = ( -pod_d / 2 + decor_d - dr_back_t + 0.5 mm ) - ( -pod_d / 2 + decor_d - dr_back_t - fr_t_pnl - 1 mm )"
equation "d9353 = sk_ref"
equation "d9354 = sk_ref"
equation "d9355 = ( dr_pl6x + ( dr_pl0x - dr_pl6x ) * ( ( dr_sc_clear + 0 * ( dr_pe6 - dr_sc_clear - dr_sc_col ) / 4 ) / dr_pe6 ) ) + sk_ref"
equation "d9356 = ( dr_pl6z + ( dr_pl0z - dr_pl6z ) * ( ( dr_sc_clear + 0 * ( dr_pe6 - dr_sc_clear - dr_sc_col ) / 4 ) / dr_pe6 ) ) + sk_ref"
equation "d9357 = fr_hole_rn"
equation "d9358 = ( dr_pl6x + ( dr_pl0x - dr_pl6x ) * ( ( dr_sc_clear + 1 * ( dr_pe6 - dr_sc_clear - dr_sc_col ) / 4 ) / dr_pe6 ) ) + sk_ref"
equation "d9359 = ( dr_pl6z + ( dr_pl0z - dr_pl6z ) * ( ( dr_sc_clear + 1 * ( dr_pe6 - dr_sc_clear - dr_sc_col ) / 4 ) / dr_pe6 ) ) + sk_ref"
equation "d9360 = fr_hole_rn"
equation "d9361 = ( dr_pl6x + ( dr_pl0x - dr_pl6x ) * ( ( dr_sc_clear + 2 * ( dr_pe6 - dr_sc_clear - dr_sc_col ) / 4 ) / dr_pe6 ) ) + sk_ref"
equation "d9362 = ( dr_pl6z + ( dr_pl0z - dr_pl6z ) * ( ( dr_sc_clear + 2 * ( dr_pe6 - dr_sc_clear - dr_sc_col ) / 4 ) / dr_pe6 ) ) + sk_ref"
equation "d9363 = fr_hole_rn"
equation "d9364 = ( dr_pl6x + ( dr_pl0x - dr_pl6x ) * ( ( dr_sc_clear + 3 * ( dr_pe6 - dr_sc_clear - dr_sc_col ) / 4 ) / dr_pe6 ) ) + sk_ref"
equation "d9365 = ( dr_pl6z + ( dr_pl0z - dr_pl6z ) * ( ( dr_sc_clear + 3 * ( dr_pe6 - dr_sc_clear - dr_sc_col ) / 4 ) / dr_pe6 ) ) + sk_ref"
equation "d9366 = fr_hole_rn"
equation "d9367 = ( dr_pl6x + ( dr_pl0x - dr_pl6x ) * ( ( dr_sc_clear + 4 * ( dr_pe6 - dr_sc_clear - dr_sc_col ) / 4 ) / dr_pe6 ) ) + sk_ref"
equation "d9368 = ( dr_pl6z + ( dr_pl0z - dr_pl6z ) * ( ( dr_sc_clear + 4 * ( dr_pe6 - dr_sc_clear - dr_sc_col ) / 4 ) / dr_pe6 ) ) + sk_ref"
equation "d9369 = fr_hole_rn"
equation "d9370 = ( -pod_d / 2 + decor_d - dr_back_t - fr_t_pnl - 1 mm ) * ( 1 )"
equation "d9371 = ( -pod_d / 2 + decor_d - dr_back_t + 0.5 mm ) - ( -pod_d / 2 + decor_d - dr_back_t - fr_t_pnl - 1 mm )"
equation "d9373 = sk_ref"
equation "d9374 = sk_ref"
equation "d9375 = ( dr_sp_x1 ) + sk_ref"
equation "d9376 = ( ( -pod_d / 2 + decor_d - dr_back_t - fr_w / 2 ) ) + sk_ref"
equation "d9377 = sp_hole"
equation "d9378 = ( dr_sp_x2 - ( sp_slot - sp_hole ) / 2 ) + sk_ref"
equation "d9379 = ( ( -pod_d / 2 + decor_d - dr_back_t - fr_w / 2 ) ) + sk_ref"
equation "d9380 = sp_hole"
equation "d9381 = ( dr_sp_x2 + ( sp_slot - sp_hole ) / 2 ) + sk_ref"
equation "d9382 = ( ( -pod_d / 2 + decor_d - dr_back_t - fr_w / 2 ) ) + sk_ref"
equation "d9383 = sp_hole"
equation "d9384 = ( fg_vis_zb - 1 mm ) * ( 1 )"
equation "d9385 = ( fg_vis_zb + fr_t_pnl + 0.5 mm ) - ( fg_vis_zb - 1 mm )"
equation "d9387 = sk_ref"
equation "d9388 = sk_ref"
equation "d9389 = ( dr_sp_x2 + ( sp_slot - sp_hole ) / 2 ) + sk_ref"
equation "d9390 = ( dr_sp_x2 - ( sp_slot - sp_hole ) / 2 ) + sk_ref"
equation "d9391 = ( ( -pod_d / 2 + decor_d - dr_back_t - fr_w / 2 ) - sp_hole / 2 ) + sk_ref"
equation "d9392 = ( ( -pod_d / 2 + decor_d - dr_back_t - fr_w / 2 ) + sp_hole / 2 ) + sk_ref"
equation "d9393 = ( fg_vis_zb - 1 mm ) * ( 1 )"
equation "d9394 = ( fg_vis_zb + fr_t_pnl + 0.5 mm ) - ( fg_vis_zb - 1 mm )"
equation "d9396 = sk_ref"
equation "d9397 = sk_ref"
equation "d9398 = ( dt_sp_x1 ) + sk_ref"
equation "d9399 = ( dt_sp_y ) + sk_ref"
equation "d9400 = fr_hole_rn"
equation "d9401 = ( dt_sp_x1 + dt_sp_dx ) + sk_ref"
equation "d9402 = ( dt_sp_y ) + sk_ref"
equation "d9403 = fr_hole_rn"
equation "d9404 = ( fg_vis_zt - fr_t_rn - 0.5 mm ) * ( 1 )"
equation "d9405 = ( fg_vis_zt + 1 mm ) - ( fg_vis_zt - fr_t_rn - 0.5 mm )"
named bodies: "DR SKIN ACP 3", "DR BACK PLATE AL 2", "DR INNER FACE PANEL AL 3", "DR INNER FACE PANEL FELT 9", "848013 PANEL SEAL 4.0 SQUEEZED TO 2.36", "RESERVED AIR SPACE - INTAKE RISER (AIR 611501)", "RESERVED AIR SPACE - LOWER TRANSITION (AIR 618103)", "RESERVED AIR SPACE - SUPPLY FAN BOX (AIR 610401)", "RESERVED AIR SPACE - UPPER TRANSITION (AIR 618102)", "RESERVED AIR SPACE - UPPER TRANSITION DROP (AIR 618102)", "F01 FRONT RING BOTTOM 20 x 20 x 1.0", "F02 FRONT RING FACET SIDE 20 x 20 x 1.0", "F03 FRONT RING TOP 20 x 20 x 1.0", "F04 FRONT RING DT JOINT 20 x 20 x 1.0", "F05 FRONT RING DIAGONAL 20 x 20 x 1.0", "F06 FRONT RING GLASS EDGE 20 x 20 x 1.0", "B01 BACK RING BOTTOM 40 x 20 x 1.5", "B02 BACK RING BOLT LINE 80 x 20 x 1.5", "B03 BACK RING TOP 20 x 20 x 1.0", "B04 BACK RING DT JOINT 20 x 20 x 1.0", "B05 BACK RING DT LEDGE 20 x 20 x 1.5", "B06 BACK RING DIAGONAL 20 x 20 x 1.5", "B07 BACK RING GLASS EDGE 20 x 20 x 1.5", "F07 FRONT RING CROSS 724 20 x 20 x 1.0", "F08 FRONT RING FAN BOX SHELF 20 x 20 x 1.5", "F09 FRONT RING CROSS OVER THE FAN BOX 20 x 20 x 1.0", "B08 BACK RING BAND 60 x 20 x 1.5", "C01 FACET TUBE BOTTOM 20 x 20 x 1.0", "C03 FACET TUBE FAN BOX SHELF 20 x 20 x 1.5", "C06 CHAMFER TUBE LEFT 20 x 20 x 1.0", "C09 DT JOINT TUBE SLANTED 20 x 20 x 1.0"
